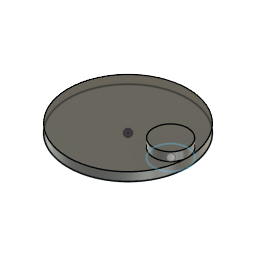
Crank (Autodesk Fusion 360 design; units mm, degrees)
Autodesk Fusion 360 part; units mm, degrees
sketch "Sketch1" plane through (0, 0, 0) normal (0, 0, 1) x (1, 0, 0)
  circle A0 centre (0, 0) radius 35
  circle A1 centre (25, 0) radius 10
  dimension "d1" = 70
  dimension "d11" = 20
  dimension "d12" = 25
  constraint coincident A0.centre origin
  measures "d1" diameter of A0
  measures "d11" diameter of A1
  measures "d12" distance of A0.centre A1.centre
extrude "Extrude1" add sketch "Sketch1" along normal blind 5 contours A0 | A1
extrude "Extrude2" add sketch "Sketch1" along normal blind 10 contours A1
sketch "Sketch2" plane through (0, 0, 0) normal (0, 0, 1) x (1, 0, 0)
  circle A0 centre (0, 0) radius 7.5
  dimension "d8" = 15
  constraint coincident A0.centre origin
  measures "d8" diameter of A0
extrude "Extrude3" add sketch "Sketch2" against normal blind 5
